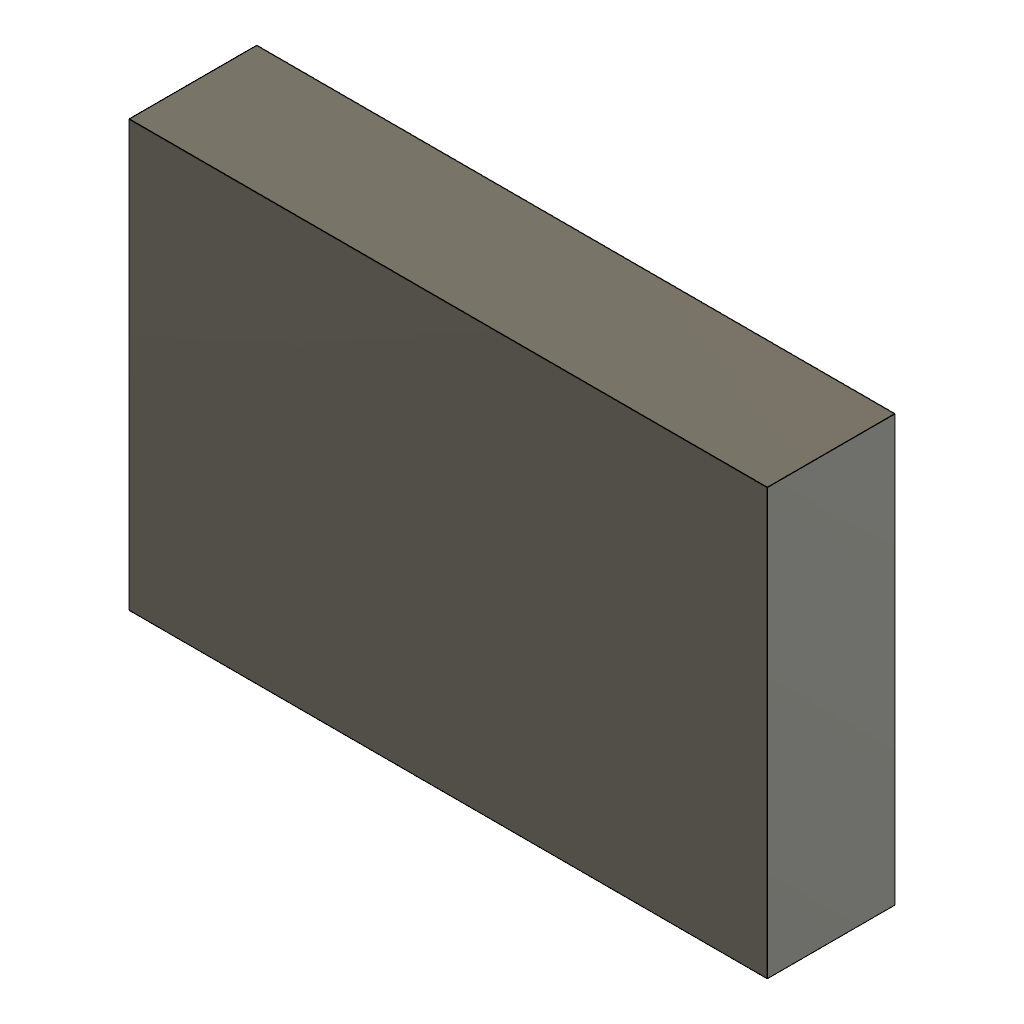
scale_body_uniform (Autodesk Fusion 360 design; units mm, degrees)
part number: 2026-11-13-14-47-56-560
Autodesk Fusion 360 part; units mm, degrees
sketch "Sketch1" plane through (0, 0, 0) normal (0, 0, 1) x (1, 0, 0)
  line L0 (0, 0) -> (30, 0)
  line L1 (30, 0) -> (30, 20)
  line L2 (30, 20) -> (0, 20)
  line L3 (0, 20) -> (0, 0)
extrude "Extrude1" add sketch "Sketch1" along normal blind 6
scale "Scale1" factor 1.5 about (0, 0, 0) bodies 1
